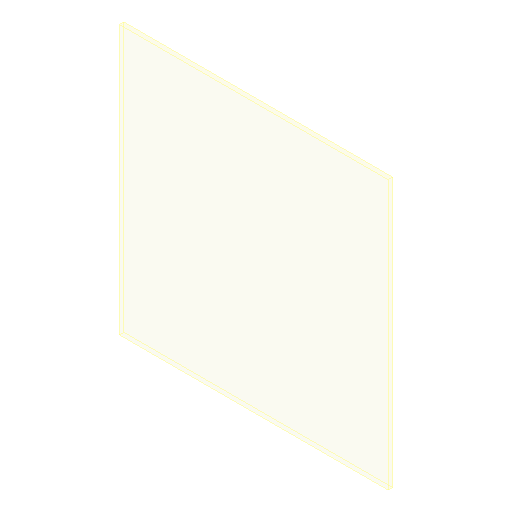
# Autodesk Inventor part: Placa
Saved by Autodesk Inventor 2025.2 (Build 292293000, 293)
## iProperties
Created: 2026-09-21
Part Number: Placa
Material: Policarbonato, claro
Document SubType Name: Modeling
Designer: autor
Density: 1.2 g/cm^3
Appearance: Claro - Amarillo
Author: autor
Autodesk Inventor part; units mm, degrees
ref_plane "YZ Plane" through (0, 0, 0) normal (1, 0, 0) x (0, 1, 0)
ref_plane "XZ Plane" through (0, 0, 0) normal (0, 1, 0) x (-1, 0, 0)
ref_plane "XY Plane" through (0, 0, 0) normal (0, 0, 1) x (1, 0, 0)
sketch "Boceto1" plane through (0, 0, 0) normal (0, 0, 1) x (1, 0, 0)
  line L0 (-19.7455, 11.0657) -> (160.2545, 11.0657)
  line L1 (160.2545, 11.0657) -> (160.2545, -168.9343)
  line L2 (160.2545, -168.9343) -> (-19.7455, -168.9343)
  line L3 (-19.7455, -168.9343) -> (-19.7455, 11.0657)
  point P0 (0, 0)
  dimension "d0" = 180
  dimension "d1" = 180
  constraints: 8 end point, 2 parallel, 1 horizontal, 1 perpendicular
  measures "d0" distance of L1.end L2.end
  measures "d1" distance of L0.end L1.end
extrude "Extrusión1" add sketch "Boceto1" along normal blind 3
